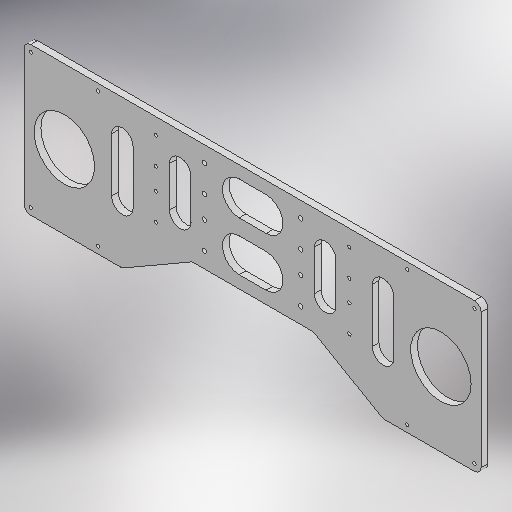
# Autodesk Inventor part: AP5.0_motor-base
Saved by Autodesk Inventor 2025.3 (Build 293356030, 356C)
## iProperties
Created: 2026-06-07
Part Number: AP5.0_motor-base
Material: 一般
Document SubType Name: Sheet Metal
Designer: ibuki_ono
Density: 1 g/cm^3
Sheet Metal Rule: Default_mm
Appearance: 既定
Author: ibuki_ono
Autodesk Inventor part; units mm, degrees
ref_plane "YZ Plane" through (0, 0, 0) normal (1, 0, 0) x (0, 1, 0)
ref_plane "XZ Plane" through (0, 0, 0) normal (0, 1, 0) x (-1, 0, 0)
ref_plane "XY Plane" through (0, 0, 0) normal (0, 0, 1) x (1, 0, 0)
sketch "スケッチ1" plane through (0, 0, 0) normal (0, 0, 1) x (1, 0, 0)
  line L0 (-50, -70) -> (50, -70)
  line L1 (50, -70) -> (50, 70)
  line L2 (50, 70) -> (-50, 70)
  line L3 (-50, 70) -> (-50, -70)
  line L4 (-50, -70) -> (50, 70) construction
  line L5 (50, -70) -> (-50, 70) construction
  line L6 (-170, -70) -> (170, -70)
  line L7 (170, -70) -> (170, 40)
  line L8 (170, 40) -> (-170, 40)
  line L9 (-170, 40) -> (-170, -70)
  line L10 (-170, -70) -> (170, 40) construction
  line L11 (170, -70) -> (-170, 40) construction
  line L12 (-170, 40) -> (-50, 70)
  line L13 (50, 70) -> (170, 40)
  point P0 (0, 0)
  point P1 (0, -15)
  point P2 (50, -70)
  dimension "d0" = 100
  dimension "d1" = 140
  dimension "d2" = 340
  dimension "d3" = 110
  measures "d0" distance of L2.end L1.end
  measures "d1" distance of L1.end L0.end
  measures "d2" distance of L8.end L7.end
  measures "d3" distance of L7.end L6.end
extrude "プレート1" add sketch "スケッチ1" along normal blind 5
sketch "スケッチ2" plane through (0, 0, 5) normal (0, 0, 1) x (1, 0, 0)
  line L0 (-35.8, 28.3) -> (-35.8, 8.3) construction
  line L1 (-35.8, 28.3) -> (-15.8, 28.3) construction
  point P0 (0, 0)
  dimension "d5" = 20
  dimension "d6" = 90
  dimension "d7" = 35.8
  dimension "d8" = 28.3
  constraints: 4 end point, 2 coincident, 1 horizontal, 1 perpendicular, 1 vertical
  measures "d5" distance of L0.start L0.end
  measures "d6" angle of L0 L1
  measures "d7" distance from line of point (0, 0) L0
  measures "d8" vertical distance of point (0, 0) L0.start
hole "穴1" at (-35.8, 28.3, 5) at (-35.8, 8.3, 5) direction (0, 0, -1) diameter 3.2 end through all
mirror "ミラー1" about plane through (0, 0, 0) normal (1, 0, 0) of "穴1"
mirror "ミラー2" about plane through (0, 0, 0) normal (0, 1, 0) of "穴1", "ミラー1"
sketch "スケッチ3" plane through (0, 0, 5) normal (0, 0, 1) x (1, 0, 0)
  line L0 (115, -65) -> (165, -65) construction
  line L1 (165, -65) -> (165, 35) construction
  line L2 (165, 35) -> (115, 35) construction
  line L3 (115, 35) -> (115, -65) construction
  line L4 (115, -65) -> (165, 35) construction
  line L5 (165, -65) -> (115, 35) construction
  line L6 (170, -70) -> (-170, -70) construction
  line L7 (170, 40) -> (170, -70) construction
  point P0 (0, 0)
  point P1 (140, -15)
  dimension "d16" = 50
  dimension "d17" = 100
  dimension "d18" = 5
  dimension "d19" = 5
  constraints: 12 end point, 3 coincident, 2 midpoint, 2 parallel, 1 horizontal, 1 perpendicular, 1 point on line
  measures "d16" distance of L2.end L1.end
  measures "d17" distance of L1.end L0.end
  measures "d18" distance between parallel lines of L6 L0
  measures "d19" distance between parallel lines of L7 L1
hole "穴2" at (115, -65, 5) at (165, -65, 5) at (165, 35, 5) at (115, 35, 5) direction (0, 0, -1) diameter 2.5 end through all
mirror "ミラー3" about plane through (0, 0, 0) normal (1, 0, 0) of "穴2"
sketch "スケッチ4" plane through (0, 0, 5) normal (0, 0, 1) x (1, 0, 0)
  circle A0 centre (-165, 35) radius 1.25 projected
  circle A1 centre (-115, -65) radius 1.25 projected
  line L0 (-165, 35) -> (-115, -65) construction
  circle A2 centre (-140, -15) radius 22.5
  circle A3 centre (115, -65) radius 1.25 projected
  circle A4 centre (165, 35) radius 1.25 projected
  circle A5 centre (115, -65) radius 1.25 construction
  line L1 (115, -65) -> (165, 35) construction
  circle A6 centre (140, -15) radius 22.5
  circle A7 centre (-35.8, 28.3) radius 1.6 projected
  circle A8 centre (35.8, 8.3) radius 1.6 projected
  circle A9 centre (-35.8, -8.3) radius 1.6 projected
  circle A10 centre (35.8, -28.3) radius 1.6 projected
  line L2 (-35.8, 28.3) -> (35.8, 8.3) construction
  line L3 (-35.8, -8.3) -> (35.8, -28.3) construction
  line L4 (-10, 18.3) -> (10, 18.3) construction
  line L5 (-10, 5.8) -> (10, 5.8)
  line L6 (10, 30.8) -> (-10, 30.8)
  arc A11 (-10, 30.8) -> (-10, 5.8) centre (-10, 18.3) ccw
  arc A12 (10, 5.8) -> (10, 30.8) centre (10, 18.3) ccw
  line L7 (0, 18.3) -> (20, 18.3) construction
  line L8 (-10, -18.3) -> (10, -18.3) construction
  line L9 (-10, -30.8) -> (10, -30.8)
  line L10 (10, -5.8) -> (-10, -5.8)
  arc A13 (-10, -5.8) -> (-10, -30.8) centre (-10, -18.3) ccw
  arc A14 (10, -30.8) -> (10, -5.8) centre (10, -18.3) ccw
  line L11 (0, -18.3) -> (20, -18.3) construction
  point P0 (0, 0)
  dimension "d27" = 45
  dimension "d31" = 45
  dimension "d35" = 10
  dimension "d36" = 0
  dimension "d37" = 25
  dimension "d38" = 10
  dimension "d39" = 0
  dimension "d40" = 25
  constraints: 28 end point, 8 point on circle, 8 tangent, 6 centre point, 6 midpoint, 3 horizontal, 3 parallel, 2 collinear
  measures "d27" diameter of A2
  measures "d31" diameter of A6
  measures "d35" distance of L7.start L4.end
  measures "d36" distance between parallel lines of L4 L7
  measures "d37" diameter of A12
  measures "d38" distance of L11.start L8.end
  measures "d39" distance between parallel lines of L8 L11
  measures "d40" diameter of A14
extrude "押し出し1" cut sketch "スケッチ4" against normal blind 10 contours A2 | A6 | A11 L6 A12 L5 | A13 L10 A14 L9
sketch "スケッチ5" plane through (0, 0, 0) normal (0, 0, -1) x (-1, 0, 0)
  line L0 (-72, -28) -> (72, -28) construction
  line L1 (72, -28) -> (72, 28) construction
  line L2 (72, 28) -> (-72, 28) construction
  line L3 (-72, 28) -> (-72, -28) construction
  line L4 (-72, -28) -> (72, 28) construction
  line L5 (72, -28) -> (-72, 28) construction
  point P0 (0, 0)
  point P1 (-72, -8)
  point P2 (-72, 8)
  point P3 (72, 8)
  point P4 (72, -8)
  dimension "d41" = 144
  dimension "d42" = 56
  dimension "d43" = 20
  dimension "d44" = 20
  dimension "d45" = 20
  dimension "d46" = 20
  constraints: 12 end point, 4 coincident, 4 point on line, 2 midpoint, 2 parallel, 1 horizontal, 1 perpendicular
  measures "d41" distance of L2.end L1.end
  measures "d42" distance of L1.end L0.end
  measures "d43" distance of point (-72, 28) point (-72, 8)
  measures "d44" distance of L0.start point (-72, -8)
  measures "d45" distance of point (72, -28) point (72, -8)
  measures "d46" distance of point (72, 28) point (72, 8)
hole "穴3" at (72, 28, 0) at (-72, 28, 0) at (-72, -28, 0) at (72, -28, 0) at (72, -8, 0) at (72, 8, 0) at (-72, 8, 0) at (-72, -8, 0) direction (0, 0, 1) diameter 2.5 end through all
sketch "スケッチ6" plane through (0, 0, 0) normal (0, 0, -1) x (-1, 0, 0)
  line L0 (-170, 40) -> (-50, 70) projected
  line L1 (-50, 70) -> (50, 70) projected
  line L2 (50, 70) -> (170, 40) projected
  line L3 (170, -70) -> (-170, -70) projected
  line L4 (-96.9615, -70) -> (-45, -40)
  line L5 (-45, -40) -> (45, -40)
  line L6 (45, -40) -> (96.9615, -70)
  line L7 (-170, -70) -> (-170, 40) projected
  line L8 (170, 40) -> (-170, 40)
  line L9 (10, -30.8) -> (-10, -30.8) projected
  point P0 (0, 0)
  point P1 (0, -40)
  dimension "d55" = 90
  dimension "d56" = 30
  dimension "d57" = 30
  dimension "d61" = 9.2
  constraints: 8 end point, 2 horizontal, 2 point on line, 1 midpoint, 1 vertical alignment
  measures "d55" distance of L4.end L5.end
  measures "d56" angle of L3 L4
  measures "d57" angle of L3 L6
  measures "d61" distance between parallel lines of L5 L9
extrude "押し出し2" cut sketch "スケッチ6" against normal through all
fillet "フィレット2" radius 5 6 edges at (170, -70, 2.5) (45, -40, 2.5) (-45, -40, 2.5) (-170, -70, 2.5) (-170, 40, 2.5) (170, 40, 2.5)
sketch "スケッチ7" plane through (0, 0, 0) normal (0, 0, -1) x (-1, 0, 0)
  circle A0 centre (-72, 28) radius 1.25 projected
  circle A1 centre (-35.8, -28.3) radius 1.6 projected
  circle A2 centre (35.8, -28.3) radius 1.6 projected
  circle A3 centre (72, 28) radius 1.25 projected
  line L0 (-72, 28) -> (-35.8, -28.3) construction
  line L1 (35.8, -28.3) -> (72, 28) construction
  line L2 (-53.9, -15.15) -> (-53.9, 14.85) construction
  line L3 (-45.9, -15.15) -> (-45.9, 14.85)
  line L4 (-61.9, 14.85) -> (-61.9, -15.15)
  arc A4 (-61.9, -15.15) -> (-45.9, -15.15) centre (-53.9, -15.15) ccw
  arc A5 (-45.9, 14.85) -> (-61.9, 14.85) centre (-53.9, 14.85) ccw
  line L5 (-53.9, -0.15) -> (-23.9, -0.15) construction
  line L6 (53.9, -15.15) -> (53.9, 14.85) construction
  line L7 (61.9, -15.15) -> (61.9, 14.85)
  line L8 (45.9, 14.85) -> (45.9, -15.15)
  arc A6 (45.9, -15.15) -> (61.9, -15.15) centre (53.9, -15.15) ccw
  arc A7 (61.9, 14.85) -> (45.9, 14.85) centre (53.9, 14.85) ccw
  line L9 (53.9, -0.15) -> (83.9, -0.15) construction
  circle A8 centre (-140, -15) radius 22.5 projected
  circle A9 centre (140, -15) radius 22.5 projected
  line L10 (-53.9, -0.15) -> (-140, -15) construction
  line L11 (53.9, -0.15) -> (140, -15) construction
  line L12 (-96.95, -27.575) -> (-96.95, 12.425) construction
  line L13 (-88.95, -27.575) -> (-88.95, 12.425)
  line L14 (-104.95, 12.425) -> (-104.95, -27.575)
  arc A10 (-104.95, -27.575) -> (-88.95, -27.575) centre (-96.95, -27.575) ccw
  arc A11 (-88.95, 12.425) -> (-104.95, 12.425) centre (-96.95, 12.425) ccw
  line L15 (-96.95, -7.575) -> (-56.95, -7.575) construction
  line L16 (96.95, -27.575) -> (96.95, 12.425) construction
  line L17 (104.95, -27.575) -> (104.95, 12.425)
  line L18 (88.95, 12.425) -> (88.95, -27.575)
  arc A12 (88.95, -27.575) -> (104.95, -27.575) centre (96.95, -27.575) ccw
  arc A13 (104.95, 12.425) -> (88.95, 12.425) centre (96.95, 12.425) ccw
  line L19 (96.95, -7.575) -> (136.95, -7.575) construction
  point P0 (0, 0)
  dimension "d62" = 15
  dimension "d63" = 90
  dimension "d64" = 16
  dimension "d65" = 15
  dimension "d66" = 90
  dimension "d67" = 16
  dimension "d68" = 20
  dimension "d69" = 90
  dimension "d70" = 16
  dimension "d71" = 20
  dimension "d72" = 90
  dimension "d73" = 16
  constraints: 48 end point, 16 point on circle, 16 tangent, 8 centre point, 8 midpoint, 6 parallel, 4 horizontal, 4 perpendicular, 2 vertical
  measures "d62" distance of L5.start L2.end
  measures "d63" angle of L5 L2
  measures "d64" diameter of A5
  measures "d65" distance of L9.start L6.end
  measures "d66" angle of L9 L6
  measures "d67" diameter of A7
  measures "d68" distance of L15.start L12.end
  measures "d69" angle of L15 L12
  measures "d70" diameter of A11
  measures "d71" distance of L19.start L16.end
  measures "d72" angle of L19 L16
  measures "d73" diameter of A13
extrude "押し出し3" cut sketch "スケッチ7" against normal through all contours A4 L4 A5 L3 | A6 L8 A7 L7 | A10 L14 A11 L13 | A12 L18 A13 L17
equation "\"d14\" = Thickness"
equation "\"d27\" = d31"
equation "\"d44\" = d43"
equation "\"d45\" = d43"
equation "\"d46\" = d43"
equation "\"d52\" = Thickness"
equation "\"d57\" = d56"
equation "\"d4\" = Thickness"
equation "\"BendRadius\" = Thickness"
equation "\"BendReliefWidth\" = Thickness"
equation "\"BendReliefDepth\" = 0.5 * Thickness"
equation "\"TransitionRadius\" = BendRadius"
equation "\"JacobiRadiusSize\" = BendRadius"
equation "\"GapSize\" = Thickness"
equation "\"Thickness\" = 5"
